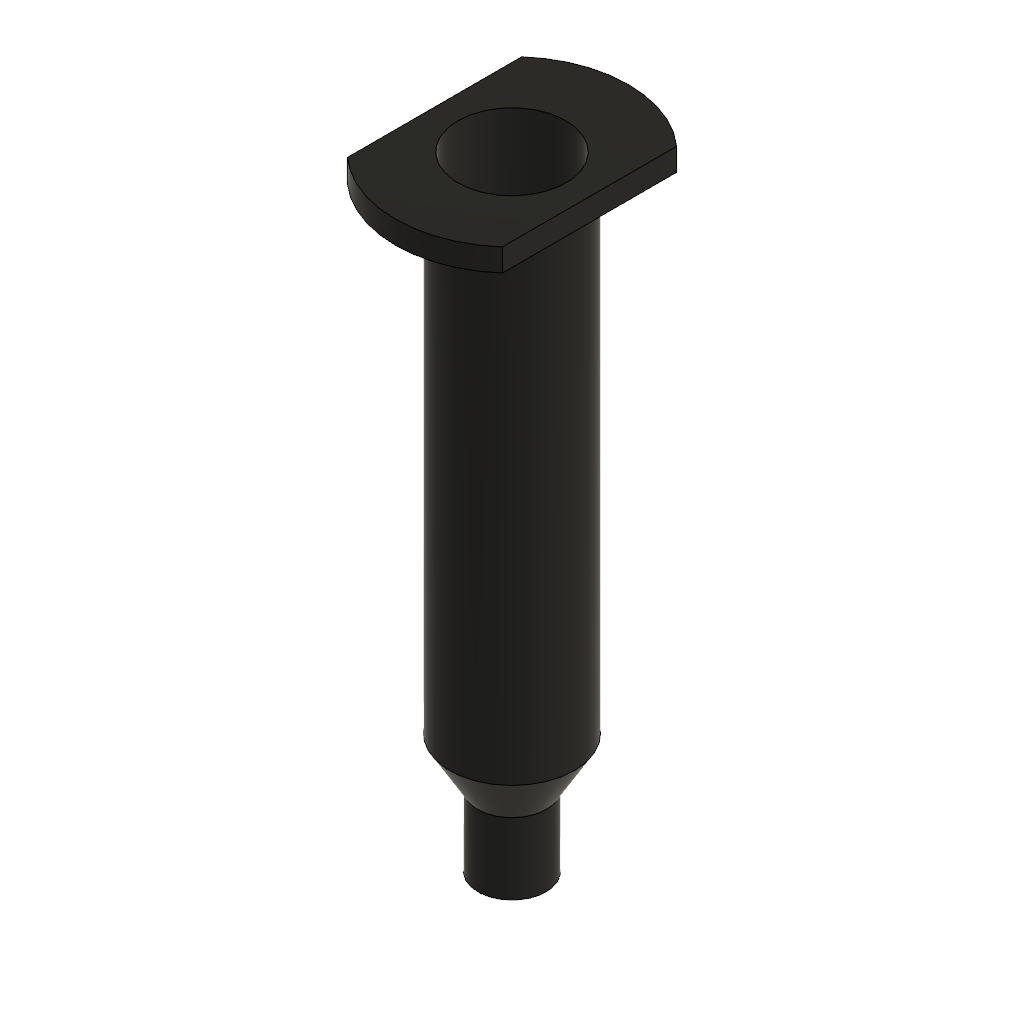
Metcal 910 süstal 10cc (Autodesk Fusion 360 design; units mm, degrees)
Autodesk Fusion 360 part; units mm, degrees
ref_plane "WorkPlane1" through (0, 0, -3.3) normal (0, 0, 1) x (1, 0, 0)
ref_plane "WorkPlane2" through (0, 0, -73.5) normal (0, 0, 1) x (1, 0, 0)
ref_plane "WorkPlane3" through (0, 0, -80.5) normal (0, 0, 1) x (1, 0, 0)
sketch "Sketch1" plane through (0, 0, 0) normal (0, 0, 1) x (1, 0, 0)
  circle A0 centre (0, 0) radius 17
  dimension "d21" = 34
  constraint coincident A0.centre origin
  measures "d21" diameter of A0
extrude "Krae" add sketch "Sketch1" against normal blind 3.3
sketch "Krae lamedad kuljed" plane through (0, 0, 0) normal (0, 0, 1) x (1, 0, 0)
  line L0 (11.3, 19) -> (-11.3, 19)
  line L1 (-11.3, 19) -> (-11.3, -17)
  line L2 (-11.3, -17) -> (11.3, -17)
  line L3 (11.3, -17) -> (11.3, 19)
  dimension "d24" = 22.6
  dimension "d25" = 36
  measures "d24" horizontal distance of L0.start L0.end
  measures "d25" vertical distance of L0.end L1.end
extrude "Krae lamedad kuljed (1)" cut sketch "Krae lamedad kuljed" against normal blind 3.3 keep common part
sketch "Sketch3" plane through (0, 0, -3.3) normal (0, 0, 1) x (1, 0, 0)
  circle A0 centre (0, 0) radius 9.13
  dimension "d28" = 18.26
  constraint coincident A0.centre origin
  measures "d28" diameter of A0
extrude "Silinder" add sketch "Sketch3" against normal blind 70.2
sketch "Sketch4" plane through (0, 0, -73.5) normal (0, 0, 1) x (1, 0, 0)
  circle A0 centre (0, 0) radius 9.13
  dimension "d31" = 18.26
  constraint coincident A0.centre origin
  measures "d31" diameter of A0
sketch "Sketch5" plane through (0, 0, -80.5) normal (0, 0, 1) x (1, 0, 0)
  circle A0 centre (0, 0) radius 5
  dimension "d32" = 10
  constraint coincident A0.centre origin
  measures "d32" diameter of A0
loft "Koonus" add profiles "Sketch4", "Sketch5" section 1 section 2
sketch "Sketch6" plane through (0, 0, -80.5) normal (0, 0, 1) x (1, 0, 0)
  circle A0 centre (0, 0) radius 5
  circle A1 centre (0, 0) radius 3.8
  dimension "d33" = 10
  dimension "d34" = 7.6
  constraint coincident A0.centre A1.centre
  measures "d33" diameter of A0
  measures "d34" diameter of A1
extrude "Luer-krae" add sketch "Sketch6" against normal blind 10.4
sketch "Sketch7" plane through (0, 0, -80.5) normal (0, 0, 1) x (1, 0, 0)
  circle A0 centre (0, 0) radius 1.95
  dimension "d37" = 3.9
  constraint coincident A0.centre origin
  measures "d37" diameter of A0
extrude "Otsiku koonus" add sketch "Sketch7" against normal blind 8.18
sketch "Sketch8" plane through (0, 0, 0) normal (0, 0, 1) x (1, 0, 0)
  circle A0 centre (0, 0) radius 7.86
  dimension "d40" = 15.72
  constraint coincident A0.centre origin
  measures "d40" diameter of A0
extrude "Sisemus" cut sketch "Sketch8" against normal blind 73.5
sketch "Sketch9" plane through (0, 0, -73.5) normal (0, 0, 1) x (1, 0, 0)
  circle A0 centre (0, 0) radius 7.86
  dimension "d43" = 15.72
  constraint coincident A0.centre origin
  measures "d43" diameter of A0
sketch "Sketch10" plane through (0, 0, -80.5) normal (0, 0, 1) x (1, 0, 0)
  circle A0 centre (0, 0) radius 1.25
  dimension "d44" = 2.5
  constraint coincident A0.centre origin
  measures "d44" diameter of A0
loft "Sisemine koonus" cut profiles "Sketch9", "Sketch10" section 1 section 2
sketch "Sketch11" plane through (0, 0, -80.5) normal (0, 0, 1) x (1, 0, 0)
  circle A0 centre (0, 0) radius 1.25
  dimension "d45" = 2.5
  constraint coincident A0.centre origin
  measures "d45" diameter of A0
extrude "Ava" cut sketch "Sketch11" against normal blind 8.18
equation "len_total = 90.9 mm" comment "kogupikkus krae tagapinnast Luer-krae otsani (andmeleht B)"
equation "flange_t = 3.3 mm" comment "krae paksus (andmeleht C)"
equation "bore_ID = 15.72 mm" comment "sisediameeter (andmeleht D)"
equation "barrel_OD = 18.26 mm" comment "valisdiameeter (andmeleht E)"
equation "flange_W = 22.6 mm" comment "krae laius ule lamedate kulgede (andmeleht F)"
equation "flange_L = 34.0 mm" comment "krae pikkus (andmeleht G)"
equation "luer_len = 10.4 mm" comment "Luer-krae pikkus (andmeleht H)"
equation "tip_len = 8.18 mm" comment "otsiku koonuse pikkus krae juurest (andmeleht I)"
equation "tip_OD = 3.9 mm" comment "otsiku koonuse diameeter (andmeleht)"
equation "orifice = 2.5 mm" comment "ava diameeter (andmeleht)"
equation "luer_OD = 10 mm" comment "HINNANG, andmelehel ei ole - mooda nihikuga"
equation "luer_wall = 1.2 mm" comment "HINNANG, Luer-krae sein - mooda"
equation "taper_len = 7 mm" comment "HINNANG, koonilise ulemineku pikkus - mooda"
equation "body_len = len_total - flange_t - taper_len - luer_len" comment "silindrilise osa pikkus, arvutatud"
equation "d15 = -flange_t"
equation "d17 = -( flange_t + body_len )"
equation "d19 = -( flange_t + body_len + taper_len )"
equation "d21 = flange_L"
equation "d22 = -( flange_t )"
equation "d24 = flange_W"
equation "d25 = flange_L + 2 mm"
equation "d26 = -( flange_t )"
equation "d28 = barrel_OD"
equation "d29 = -( body_len )"
equation "d31 = barrel_OD"
equation "d32 = luer_OD"
equation "d33 = luer_OD"
equation "d34 = luer_OD - 2 * luer_wall"
equation "d35 = -( luer_len )"
equation "d37 = tip_OD"
equation "d38 = -( tip_len )"
equation "d40 = bore_ID"
equation "d41 = -( flange_t + body_len )"
equation "d43 = bore_ID"
equation "d44 = orifice"
equation "d45 = orifice"
equation "d46 = -( tip_len )"
named bodies: "Metcal 910 suestal 10 cc"
